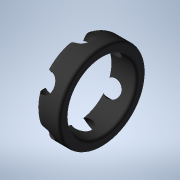
# Autodesk Inventor part: 101013DH-16-B1_cage
Saved by Autodesk Inventor 2021 (Build 250183000, 183)
## iProperties
Created: 2025-04-11
Part Number: 101013DH-16-B1_cage
Material: Generic
Catalog Web Link: www.cadenas.de
Description: DH-A,B,H cage-D-Series bearings
Vendor: TOKBEARING
Document SubType Name: Modeling
Designer: psAdmin
Manufacturer: TOKBEARING
Mass: 11800 g
Surface Area: 3.5019 cm^2
Volume: 0.156803 cm^3
Density: 1 g/cm^3
Appearance: PSOLRGB-175-175-175
Category: PARTsolutions
Company: TOKBEARING
Title: 101013DH-16-B1_cage
Author: Cadenas PARTsolutions
Comments: D-Series bearings
PSOL_IDENT_0: {$CADENAS_DATA/23d-libs/tok_bearing/d_series_bearings/dh_abh/dh_abh_cage.prj},187 {VTYP=3D},{NB=1010
PSOL_IDENT_1: 13DH-16-B1_cage},{LINA=101013DH-16-B1_cage},{NN=DH-A,B,H cage},{DATE=24.03.2025 06:05:04},{GEOMDATE=
PSOL_IDENT_2: 06.12.2012 07:31:00},{VERSION=},{LINEID=2630},{WBVAR=},{WBNUMERIC=}  {NB=101013DH-16-B1_cage},{LINA=
PSOL_IDENT_3: 101013DH-16-B1_cage},{KT=DUMMY},{IDNR=},{CODE=101013},{PN=DH-16-B1},{D=19},{D1=16.0},{SD=-},{SDX=0.0
PSOL_IDENT_4: 00},{SD1=-},{SD1X=0.000},{W=6},{C=1},{CX=1.000},{L=8},{LX=8.000},{D2XT=-},{D2=0.000},{T=0.000},{G=2.
PSOL_IDENT_5: 1},{TYPE=2},{QTY=2.000},{GW=11.8},{NDM=6.000},{BD=3},{OP=39.878},{N=6},{R=6.35},{GP=2.82}
NB: 101013DH-16-B1_cage
NN: DH-A,B,H cage
NT: D-Series bearings
NBSYN: $CODE.$PN._cage
LINA: 101013DH-16-B1_cage
CATALOG: TOK, Inc
CODE: 101013
PN: DH-16-B1
D: 19
D1: 16
SD: -
SD1: -
W: 6
C: 1
L: 8
D2XT: -
G: 2.1
TYPE: 2
QTY: 2.000
GW: 11.8
SUPPLIER: TOKBEARING
ARTICLENO: 101013DH-16-B1_cage
BOMINFO: 101013DH-16-B1_cage
CREATOR: CADENAS GmbH
Autodesk Inventor part; units mm, degrees
sketch "Sketch_1" plane through (0, 0, 0) normal (0, 0, 1) x (1, 0, 0)
  line L0 (6, 0) -> (2.1, 0)
  arc A0 (2.1, 5.2891) -> (2.2091, 5.18) centre (2.2091, 5.2891) ccw
  line L1 (2.2091, 5.18) -> (5.6, 5.18)
  arc A1 (5.6, 5.18) -> (6, 5.58) centre (5.6, 5.58) ccw
  line L2 (6, 5.58) -> (6, 6.28)
  arc A2 (6, 6.28) -> (5.6, 6.68) centre (5.6, 6.28) ccw
  line L3 (5.6, 6.68) -> (3.3, 6.68)
  arc A3 (3.3, 6.68) -> (2.1, 5.48) centre (3.3, 5.48) ccw
  line L4 (2.1, 5.48) -> (2.1, 5.2891)
  constraints: 10 end point, 8 point on circle, 4 centre point
revolve "Revolution1" add sketch "Sketch_1" angle 360 about axis through (6, 0, 0) along (1, 0, 0)
sketch "Sketch_2" plane through (3, 0, 0) normal (1, 0, 0) x (0, 0, -1)
  line L0 (1.5, 5.93) -> (-1.5, 5.93)
  arc A0 (1.5, 5.93) -> (-1.5, 5.93) centre (0, 5.93) ccw
  line L1 (1.5, 5.93) -> (-1.5, 5.93)
  constraints: 4 end point, 2 point on circle, 1 centre point
revolve "Revolution2" cut sketch "Sketch_2" angle 360 about axis through (3, 5.93, -1.5) along (0, 0, -1)
pattern_linear "Rectangular Pattern1" count 3 spacing 5.93 along (0, -0.5, 0.866) count 3 spacing 5.93 along (0, -0.5, -0.866) of "Revolution2"
ref_plane "Cage_Ball_1_XY" through (3, 5.93, 0) normal (1, 0, 0) x (0, 0, -1)
ref_plane "Cage_Ball_1_YZ" through (3, 5.93, 0) normal (0, 0, -1) x (0, 1, 0)
ref_plane "Cage_Ball_1_ZX" through (3, 5.93, 0) normal (0, 1, 0) x (1, 0, 0)
ref_plane "Cage_Ball_2_XY" through (3, 2.965, 5.1355) normal (1, 0, 0) x (0, 0, -1)
ref_plane "Cage_Ball_2_YZ" through (3, 2.965, 5.1355) normal (0, 0, -1) x (0, 1, 0)
ref_plane "Cage_Ball_2_ZX" through (3, 2.965, 5.1355) normal (0, 1, 0) x (1, 0, 0)
ref_plane "Cage_Ball_3_XY" through (3, -2.965, 5.1355) normal (1, 0, 0) x (0, 0, -1)
ref_plane "Cage_Ball_3_YZ" through (3, -2.965, 5.1355) normal (0, 0, -1) x (0, 1, 0)
ref_plane "Cage_Ball_3_ZX" through (3, -2.965, 5.1355) normal (0, 1, 0) x (1, 0, 0)
ref_plane "Cage_Ball_4_XY" through (3, -5.93, 0) normal (1, 0, 0) x (0, 0, -1)
ref_plane "Cage_Ball_4_YZ" through (3, -5.93, 0) normal (0, 0, -1) x (0, 1, 0)
ref_plane "Cage_Ball_4_ZX" through (3, -5.93, 0) normal (0, 1, 0) x (1, 0, 0)
ref_plane "Cage_Ball_5_XY" through (3, -2.965, -5.1355) normal (1, 0, 0) x (0, 0, -1)
ref_plane "Cage_Ball_5_YZ" through (3, -2.965, -5.1355) normal (0, 0, -1) x (0, 1, 0)
ref_plane "Cage_Ball_5_ZX" through (3, -2.965, -5.1355) normal (0, 1, 0) x (1, 0, 0)
ref_plane "Cage_Ball_6_XY" through (3, 2.965, -5.1355) normal (1, 0, 0) x (0, 0, -1)
ref_plane "Cage_Ball_6_YZ" through (3, 2.965, -5.1355) normal (0, 0, -1) x (0, 1, 0)
ref_plane "Cage_Ball_6_ZX" through (3, 2.965, -5.1355) normal (0, 1, 0) x (1, 0, 0)
ref_plane "Cage_OR_XY" through (0, 0, 0) normal (1, 0, 0) x (0, 0, -1)
ref_plane "Cage_OR_YZ" through (0, 0, 0) normal (0, 0, -1) x (0, 1, 0)
ref_plane "Cage_OR_ZX" through (0, 0, 0) normal (0, 1, 0) x (1, 0, 0)
body "Solid1"
